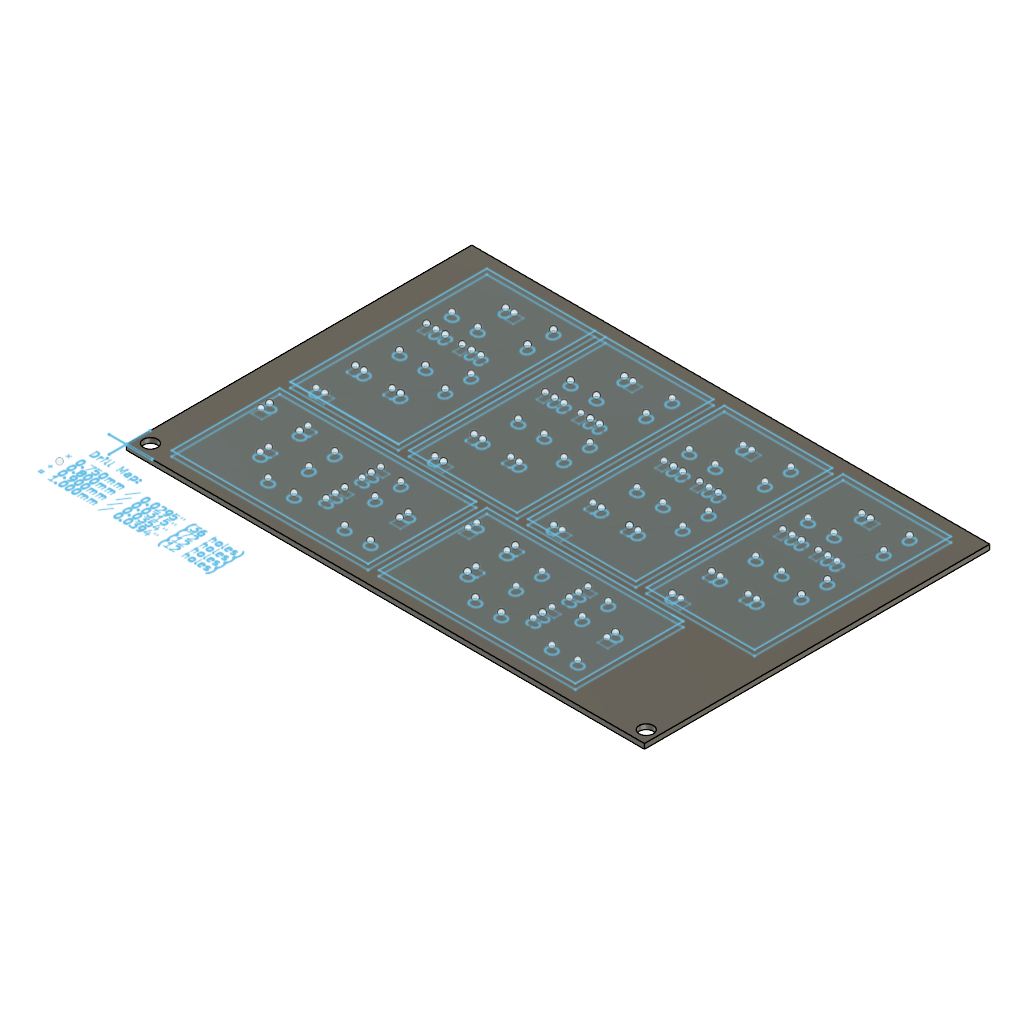
Pcb DXF's amd copper plate (Autodesk Fusion 360 archive; units mm, degrees)
design "Pcb DXF's amd copper plate"
part number: 2026-08-05-12-23-01-536
Autodesk Fusion 360 part; units mm, degrees
(part 1 of 28)
sketch "Sketch1" plane through (0, 0, 0) normal (0, 0, 1) x (1, 0, 0)
  line L0 (0, 0) -> (152.4, 0)
  line L1 (152.4, 0) -> (152.4, 101.6)
  line L2 (152.4, 101.6) -> (0, 101.6)
  line L3 (0, 101.6) -> (0, 0)
  dimension "d1" = 152.4
  dimension "d2" = 101.6
  constraint horizontal L0
  constraint vertical L1
  constraint horizontal L2
  constraint vertical L3
  constraint coincident L0.start L3.end
  measures "d1" distance of L0.start L0.end
  measures "d2" distance of L0.start L2.end
extrude "Extrude1" add sketch "Sketch1" along normal blind 1.4859
sketch "Sketch2" plane through (0, 0, 1.4859) normal (0, 0, 1) x (-1, 0, 0)
  line L0 (0, -101.6) -> (0, 0)
  line L1 (0, 0) -> (-152.4, 0)
  line L2 (-152.4, 0) -> (-152.4, -101.6)
  line L3 (-152.4, -101.6) -> (0, -101.6)
  circle A0 centre (-3.2766, -3.81) radius 2.0955
  line L4 (-3.2766, -3.81) -> (-149.1234, -3.81)
  circle A1 centre (-149.1234, -3.81) radius 2.0955
  line L5 (-76.2, -101.6) -> (-76.2, 0) construction
  line L6 (-76.2, -3.81) -> (-76.2, 5.8552) construction
  dimension "d5" = 4.191
  dimension "d8" = 145.8468
  dimension "d9" = 4.191
  constraint coincident A0.centre L4.start
  constraint perpendicular L0 L4
  constraint coincident L4.end A1.centre
  constraint midpoint L3 L5.start
  constraint midpoint L1 L5.end
  constraint midpoint L4 L6.start
  constraint perpendicular L4 L6
  measures "d5" diameter of A0
  measures "d8" distance of A0.centre L4.end
  measures "d9" diameter of A1
extrude "Extrude2" cut sketch "Sketch2" against normal blind 7.62 contours A0 | A1
sketch "Blinking Light House-Edge_Cuts" plane through (0, 0, 1.4859) normal (0, 0, 1) x (1, 0, 0)
  line L0 (0.0231, 6.9946) -> (0.025, 6.985)
  line L1 (0.025, 6.985) -> (0.025, 0.025)
  line L2 (0.025, 0.025) -> (7.62, 0.025)
  line L3 (7.62, 0.025) -> (7.6296, 0.0231)
  line L4 (7.6296, 0.0231) -> (7.6431, 0.0096)
  line L5 (7.6431, 0.0096) -> (7.6431, -0.0096)
  line L6 (7.6431, -0.0096) -> (7.6296, -0.0231)
  line L7 (7.6296, -0.0231) -> (7.62, -0.025)
  line L8 (7.62, -0.025) -> (0.025, -0.025)
  line L9 (0.025, -0.025) -> (0.025, -5.08)
  line L10 (0.025, -5.08) -> (0.0231, -5.0896)
  line L11 (0.0231, -5.0896) -> (0.0096, -5.1031)
  line L12 (0.0096, -5.1031) -> (-0.0096, -5.1031)
  line L13 (-0.0096, -5.1031) -> (-0.0231, -5.0896)
  line L14 (-0.0231, -5.0896) -> (-0.025, -5.08)
  line L15 (-0.025, -5.08) -> (-0.025, -0.025)
  line L16 (-0.025, -0.025) -> (-5.08, -0.025)
  line L17 (-5.08, -0.025) -> (-5.0896, -0.0231)
  line L18 (-5.0896, -0.0231) -> (-5.1031, -0.0096)
  line L19 (-5.1031, -0.0096) -> (-5.1031, 0.0096)
  line L20 (-5.1031, 0.0096) -> (-5.0896, 0.0231)
  line L21 (-5.0896, 0.0231) -> (-5.08, 0.025)
  line L22 (-5.08, 0.025) -> (-0.025, 0.025)
  line L23 (-0.025, 0.025) -> (-0.025, 6.985)
  line L24 (-0.025, 6.985) -> (-0.0231, 6.9946)
  line L25 (-0.0231, 6.9946) -> (-0.0096, 7.0081)
  line L26 (-0.0096, 7.0081) -> (0.0096, 7.0081)
  line L27 (0.0096, 7.0081) -> (0.0231, 6.9946)
  line L28 (66.04, 36.855) -> (66.0496, 36.8531)
  line L29 (66.0496, 36.8531) -> (66.0631, 36.8396)
  line L30 (66.0631, 36.8396) -> (66.065, 36.83)
  line L31 (66.065, 36.83) -> (66.065, 5.08)
  line L32 (66.065, 5.08) -> (66.0631, 5.0704)
  line L33 (66.0631, 5.0704) -> (66.0496, 5.0569)
  line L34 (66.0496, 5.0569) -> (66.04, 5.055)
  line L35 (66.04, 5.055) -> (8.255, 5.055)
  line L36 (8.255, 5.055) -> (8.2454, 5.0569)
  line L37 (8.2454, 5.0569) -> (8.2319, 5.0704)
  line L38 (8.2319, 5.0704) -> (8.23, 5.08)
  line L39 (8.23, 5.08) -> (8.23, 36.83)
  line L40 (8.23, 36.83) -> (8.2319, 36.8396)
  line L41 (8.2319, 36.8396) -> (8.2454, 36.8531)
  line L42 (8.2454, 36.8531) -> (8.255, 36.855)
  line L43 (8.255, 36.855) -> (66.04, 36.855)
  line L44 (8.28, 36.805) -> (8.28, 5.105)
  line L45 (8.28, 5.105) -> (66.015, 5.105)
  line L46 (66.015, 5.105) -> (66.015, 36.805)
  line L47 (66.015, 36.805) -> (62.865, 36.805)
  line L48 (62.865, 36.805) -> (8.28, 36.805)
  line L49 (127, 36.855) -> (127.0096, 36.8531)
  line L50 (127.0096, 36.8531) -> (127.0231, 36.8396)
  line L51 (127.0231, 36.8396) -> (127.025, 36.83)
  line L52 (127.025, 36.83) -> (127.025, 5.08)
  line L53 (127.025, 5.08) -> (127.0231, 5.0704)
  line L54 (127.0231, 5.0704) -> (127.0096, 5.0569)
  line L55 (127.0096, 5.0569) -> (127, 5.055)
  line L56 (127, 5.055) -> (69.215, 5.055)
  line L57 (69.215, 5.055) -> (69.2054, 5.0569)
  line L58 (69.2054, 5.0569) -> (69.1919, 5.0704)
  line L59 (69.1919, 5.0704) -> (69.19, 5.08)
  line L60 (69.19, 5.08) -> (69.19, 36.83)
  line L61 (69.19, 36.83) -> (69.1919, 36.8396)
  line L62 (69.1919, 36.8396) -> (69.2054, 36.8531)
  line L63 (69.2054, 36.8531) -> (69.215, 36.855)
  line L64 (69.215, 36.855) -> (127, 36.855)
  line L65 (69.24, 36.805) -> (69.24, 5.105)
  line L66 (69.24, 5.105) -> (126.975, 5.105)
  line L67 (126.975, 5.105) -> (126.975, 36.805)
  line L68 (126.975, 36.805) -> (123.825, 36.805)
  line L69 (123.825, 36.805) -> (69.24, 36.805)
  line L70 (43.18, 97.815) -> (74.93, 97.815)
  line L71 (74.93, 97.815) -> (74.9396, 97.8131)
  line L72 (74.9396, 97.8131) -> (74.9531, 97.7996)
  line L73 (74.9531, 97.7996) -> (74.955, 97.79)
  line L74 (74.955, 97.79) -> (74.955, 40.005)
  line L75 (74.955, 40.005) -> (74.9531, 39.9954)
  line L76 (74.9531, 39.9954) -> (74.9396, 39.9819)
  line L77 (74.9396, 39.9819) -> (74.93, 39.98)
  line L78 (74.93, 39.98) -> (43.18, 39.98)
  line L79 (43.18, 39.98) -> (43.1704, 39.9819)
  line L80 (43.1704, 39.9819) -> (43.1569, 39.9954)
  line L81 (43.1569, 39.9954) -> (43.155, 40.005)
  line L82 (43.155, 40.005) -> (43.155, 97.765)
  line L83 (40.03, 97.765) -> (40.03, 40.005)
  line L84 (40.03, 40.005) -> (40.0281, 39.9954)
  line L85 (40.0281, 39.9954) -> (40.0146, 39.9819)
  line L86 (40.0146, 39.9819) -> (40.005, 39.98)
  line L87 (40.005, 39.98) -> (8.255, 39.98)
  line L88 (8.255, 39.98) -> (8.2454, 39.9819)
  line L89 (8.2454, 39.9819) -> (8.2319, 39.9954)
  line L90 (8.2319, 39.9954) -> (8.23, 40.005)
  line L91 (8.23, 40.005) -> (8.23, 97.79)
  line L92 (8.23, 97.79) -> (8.2319, 97.7996)
  line L93 (8.2319, 97.7996) -> (8.2454, 97.8131)
  line L94 (8.2454, 97.8131) -> (8.255, 97.815)
  line L95 (8.255, 97.815) -> (40.005, 97.815)
  line L96 (43.205, 97.765) -> (43.205, 40.03)
  line L97 (43.205, 40.03) -> (74.905, 40.03)
  line L98 (74.905, 40.03) -> (74.905, 97.765)
  line L99 (74.905, 97.765) -> (43.205, 97.765)
  line L100 (8.28, 97.765) -> (8.28, 40.03)
  line L101 (8.28, 40.03) -> (39.98, 40.03)
  line L102 (39.98, 40.03) -> (39.98, 97.765)
  line L103 (39.98, 97.765) -> (8.28, 97.765)
  line L104 (109.8646, 97.8131) -> (109.8781, 97.7996)
  line L105 (109.8781, 97.7996) -> (109.88, 97.79)
  line L106 (109.88, 97.79) -> (109.88, 40.005)
  line L107 (109.88, 40.005) -> (109.8781, 39.9954)
  line L108 (109.8781, 39.9954) -> (109.8646, 39.9819)
  line L109 (109.8646, 39.9819) -> (109.855, 39.98)
  line L110 (109.855, 39.98) -> (78.105, 39.98)
  line L111 (78.105, 39.98) -> (78.0954, 39.9819)
  line L112 (78.0954, 39.9819) -> (78.0819, 39.9954)
  line L113 (78.0819, 39.9954) -> (78.08, 40.005)
  line L114 (78.08, 40.005) -> (78.08, 97.79)
  line L115 (78.08, 97.79) -> (78.0819, 97.7996)
  line L116 (78.0819, 97.7996) -> (78.0954, 97.8131)
  line L117 (78.0954, 97.8131) -> (78.105, 97.815)
  line L118 (78.105, 97.815) -> (109.855, 97.815)
  line L119 (109.855, 97.815) -> (109.8646, 97.8131)
  line L120 (78.13, 97.765) -> (78.13, 40.03)
  line L121 (78.13, 40.03) -> (109.83, 40.03)
  line L122 (109.83, 40.03) -> (109.83, 97.765)
  line L123 (109.83, 97.765) -> (78.13, 97.765)
  line L124 (144.7896, 97.8131) -> (144.8031, 97.7996)
  line L125 (144.8031, 97.7996) -> (144.805, 97.79)
  line L126 (144.805, 97.79) -> (144.805, 40.005)
  line L127 (144.805, 40.005) -> (144.8031, 39.9954)
  line L128 (144.8031, 39.9954) -> (144.7896, 39.9819)
  line L129 (144.7896, 39.9819) -> (144.78, 39.98)
  line L130 (144.78, 39.98) -> (113.03, 39.98)
  line L131 (113.03, 39.98) -> (113.0204, 39.9819)
  line L132 (113.0204, 39.9819) -> (113.0069, 39.9954)
  line L133 (113.0069, 39.9954) -> (113.005, 40.005)
  line L134 (113.005, 40.005) -> (113.005, 97.79)
  line L135 (113.005, 97.79) -> (113.0069, 97.7996)
  line L136 (113.0069, 97.7996) -> (113.0204, 97.8131)
  line L137 (113.0204, 97.8131) -> (113.03, 97.815)
  line L138 (113.03, 97.815) -> (144.78, 97.815)
  line L139 (144.78, 97.815) -> (144.7896, 97.8131)
  line L140 (113.055, 97.765) -> (113.055, 40.03)
  line L141 (113.055, 40.03) -> (144.755, 40.03)
  line L142 (144.755, 40.03) -> (144.755, 97.765)
  line L143 (144.755, 97.765) -> (113.055, 97.765)
sketch "Blinking Light House-B_Cu" plane through (0, 0, 1.4859) normal (0, 0, 1) x (1, 0, 0)
  line L0 (53.0106, 12.7385, -1.4859) -> (53.2043, 12.7078, -1.4859)
  line L1 (53.2043, 12.7078, -1.4859) -> (53.3909, 12.6472, -1.4859)
  line L2 (53.3909, 12.6472, -1.4859) -> (53.5657, 12.5581, -1.4859)
  line L3 (53.5657, 12.5581, -1.4859) -> (53.7243, 12.4428, -1.4859)
  line L4 (53.7243, 12.4428, -1.4859) -> (53.863, 12.3041, -1.4859)
  line L5 (53.863, 12.3041, -1.4859) -> (53.9783, 12.1454, -1.4859)
  line L6 (53.9783, 12.1454, -1.4859) -> (54.0674, 11.9707, -1.4859)
  line L7 (54.0674, 11.9707, -1.4859) -> (54.128, 11.7841, -1.4859)
  line L8 (54.128, 11.7841, -1.4859) -> (54.1587, 11.5904, -1.4859)
  line L9 (54.1587, 11.5904, -1.4859) -> (54.1587, 11.3942, -1.4859)
  line L10 (54.1587, 11.3942, -1.4859) -> (54.128, 11.2005, -1.4859)
  line L11 (54.128, 11.2005, -1.4859) -> (54.0674, 11.014, -1.4859)
  line L12 (54.0674, 11.014, -1.4859) -> (53.9783, 10.8392, -1.4859)
  line L13 (53.9783, 10.8392, -1.4859) -> (53.863, 10.6805, -1.4859)
  line L14 (53.863, 10.6805, -1.4859) -> (53.7243, 10.5418, -1.4859)
  line L15 (53.7243, 10.5418, -1.4859) -> (53.5657, 10.4265, -1.4859)
  line L16 (53.5657, 10.4265, -1.4859) -> (53.3909, 10.3375, -1.4859)
  line L17 (53.3909, 10.3375, -1.4859) -> (53.2043, 10.2768, -1.4859)
  line L18 (53.2043, 10.2768, -1.4859) -> (53.0106, 10.2462, -1.4859)
  line L19 (53.0106, 10.2462, -1.4859) -> (52.9125, 10.2423, -1.4859)
  line L20 (52.9125, 10.2423, -1.4859) -> (52.4125, 10.2423, -1.4859)
  line L21 (52.4125, 10.2423, -1.4859) -> (52.3145, 10.2462, -1.4859)
  line L22 (52.3145, 10.2462, -1.4859) -> (52.1207, 10.2768, -1.4859)
  line L23 (52.1207, 10.2768, -1.4859) -> (51.9342, 10.3375, -1.4859)
  line L24 (51.9342, 10.3375, -1.4859) -> (51.7594, 10.4265, -1.4859)
  line L25 (51.7594, 10.4265, -1.4859) -> (51.6007, 10.5418, -1.4859)
  line L26 (51.6007, 10.5418, -1.4859) -> (51.462, 10.6805, -1.4859)
  line L27 (51.462, 10.6805, -1.4859) -> (51.3467, 10.8392, -1.4859)
  line L28 (51.3467, 10.8392, -1.4859) -> (51.2577, 11.014, -1.4859)
  line L29 (51.2577, 11.014, -1.4859) -> (51.1971, 11.2005, -1.4859)
  line L30 (51.1971, 11.2005, -1.4859) -> (51.1664, 11.3942, -1.4859)
  line L31 (51.1664, 11.3942, -1.4859) -> (51.1664, 11.5904, -1.4859)
  line L32 (51.1664, 11.5904, -1.4859) -> (51.1971, 11.7841, -1.4859)
  line L33 (51.1971, 11.7841, -1.4859) -> (51.2577, 11.9707, -1.4859)
  line L34 (51.2577, 11.9707, -1.4859) -> (51.3467, 12.1454, -1.4859)
  line L35 (51.3467, 12.1454, -1.4859) -> (51.462, 12.3041, -1.4859)
  line L36 (51.462, 12.3041, -1.4859) -> (51.6007, 12.4428, -1.4859)
  line L37 (51.6007, 12.4428, -1.4859) -> (51.7594, 12.5581, -1.4859)
  line L38 (51.7594, 12.5581, -1.4859) -> (51.9342, 12.6472, -1.4859)
  line L39 (51.9342, 12.6472, -1.4859) -> (52.1207, 12.7078, -1.4859)
  line L40 (52.1207, 12.7078, -1.4859) -> (52.3145, 12.7385, -1.4859)
  line L41 (52.3145, 12.7385, -1.4859) -> (52.4125, 12.7423, -1.4859)
  line L42 (52.4125, 12.7423, -1.4859) -> (52.9125, 12.7423, -1.4859)
  line L43 (52.9125, 12.7423, -1.4859) -> (53.0106, 12.7385, -1.4859)
  line L44 (60.6306, 12.7385, -1.4859) -> (60.8243, 12.7078, -1.4859)
  line L45 (60.8243, 12.7078, -1.4859) -> (61.0109, 12.6472, -1.4859)
  line L46 (61.0109, 12.6472, -1.4859) -> (61.1857, 12.5581, -1.4859)
  line L47 (61.1857, 12.5581, -1.4859) -> (61.3443, 12.4428, -1.4859)
  line L48 (61.3443, 12.4428, -1.4859) -> (61.483, 12.3041, -1.4859)
  line L49 (61.483, 12.3041, -1.4859) -> (61.5983, 12.1454, -1.4859)
  line L50 (61.5983, 12.1454, -1.4859) -> (61.6874, 11.9707, -1.4859)
  line L51 (61.6874, 11.9707, -1.4859) -> (61.748, 11.7841, -1.4859)
  line L52 (61.748, 11.7841, -1.4859) -> (61.7787, 11.5904, -1.4859)
  line L53 (61.7787, 11.5904, -1.4859) -> (61.7787, 11.3942, -1.4859)
  line L54 (61.7787, 11.3942, -1.4859) -> (61.748, 11.2005, -1.4859)
  line L55 (61.748, 11.2005, -1.4859) -> (61.6874, 11.014, -1.4859)
  line L56 (61.6874, 11.014, -1.4859) -> (61.5983, 10.8392, -1.4859)
  line L57 (61.5983, 10.8392, -1.4859) -> (61.483, 10.6805, -1.4859)
  line L58 (61.483, 10.6805, -1.4859) -> (61.3443, 10.5418, -1.4859)
  line L59 (61.3443, 10.5418, -1.4859) -> (61.1857, 10.4265, -1.4859)
  line L60 (61.1857, 10.4265, -1.4859) -> (61.0109, 10.3375, -1.4859)
  line L61 (61.0109, 10.3375, -1.4859) -> (60.8243, 10.2768, -1.4859)
  line L62 (60.8243, 10.2768, -1.4859) -> (60.6306, 10.2462, -1.4859)
  line L63 (60.6306, 10.2462, -1.4859) -> (60.5325, 10.2423, -1.4859)
  line L64 (60.5325, 10.2423, -1.4859) -> (60.0325, 10.2423, -1.4859)
  line L65 (60.0325, 10.2423, -1.4859) -> (59.9345, 10.2462, -1.4859)
  line L66 (59.9345, 10.2462, -1.4859) -> (59.7407, 10.2768, -1.4859)
  line L67 (59.7407, 10.2768, -1.4859) -> (59.5542, 10.3375, -1.4859)
  line L68 (59.5542, 10.3375, -1.4859) -> (59.3794, 10.4265, -1.4859)
  line L69 (59.3794, 10.4265, -1.4859) -> (59.2207, 10.5418, -1.4859)
  line L70 (59.2207, 10.5418, -1.4859) -> (59.082, 10.6805, -1.4859)
  line L71 (59.082, 10.6805, -1.4859) -> (58.9667, 10.8392, -1.4859)
  line L72 (58.9667, 10.8392, -1.4859) -> (58.8777, 11.014, -1.4859)
  line L73 (58.8777, 11.014, -1.4859) -> (58.8171, 11.2005, -1.4859)
  line L74 (58.8171, 11.2005, -1.4859) -> (58.7864, 11.3942, -1.4859)
  line L75 (58.7864, 11.3942, -1.4859) -> (58.7864, 11.5904, -1.4859)
  line L76 (58.7864, 11.5904, -1.4859) -> (58.8171, 11.7841, -1.4859)
  line L77 (58.8171, 11.7841, -1.4859) -> (58.8777, 11.9707, -1.4859)
  line L78 (58.8777, 11.9707, -1.4859) -> (58.9667, 12.1454, -1.4859)
  line L79 (58.9667, 12.1454, -1.4859) -> (59.082, 12.3041, -1.4859)
  line L80 (59.082, 12.3041, -1.4859) -> (59.2207, 12.4428, -1.4859)
  line L81 (59.2207, 12.4428, -1.4859) -> (59.3794, 12.5581, -1.4859)
  line L82 (59.3794, 12.5581, -1.4859) -> (59.5542, 12.6472, -1.4859)
  line L83 (59.5542, 12.6472, -1.4859) -> (59.7407, 12.7078, -1.4859)
  line L84 (59.7407, 12.7078, -1.4859) -> (59.9345, 12.7385, -1.4859)
  line L85 (59.9345, 12.7385, -1.4859) -> (60.0325, 12.7423, -1.4859)
  line L86 (60.0325, 12.7423, -1.4859) -> (60.5325, 12.7423, -1.4859)
  line L87 (60.5325, 12.7423, -1.4859) -> (60.6306, 12.7385, -1.4859)
  line L88 (113.9706, 12.7385, -1.4859) -> (114.1643, 12.7078, -1.4859)
  line L89 (114.1643, 12.7078, -1.4859) -> (114.3509, 12.6472, -1.4859)
  line L90 (114.3509, 12.6472, -1.4859) -> (114.5257, 12.5581, -1.4859)
  line L91 (114.5257, 12.5581, -1.4859) -> (114.6843, 12.4428, -1.4859)
  line L92 (114.6843, 12.4428, -1.4859) -> (114.823, 12.3041, -1.4859)
  line L93 (114.823, 12.3041, -1.4859) -> (114.9383, 12.1454, -1.4859)
  line L94 (114.9383, 12.1454, -1.4859) -> (115.0274, 11.9707, -1.4859)
  line L95 (115.0274, 11.9707, -1.4859) -> (115.088, 11.7841, -1.4859)
  line L96 (115.088, 11.7841, -1.4859) -> (115.1187, 11.5904, -1.4859)
  line L97 (115.1187, 11.5904, -1.4859) -> (115.1187, 11.3942, -1.4859)
  line L98 (115.1187, 11.3942, -1.4859) -> (115.088, 11.2005, -1.4859)
  line L99 (115.088, 11.2005, -1.4859) -> (115.0274, 11.014, -1.4859)
  line L100 (115.0274, 11.014, -1.4859) -> (114.9383, 10.8392, -1.4859)
  line L101 (114.9383, 10.8392, -1.4859) -> (114.823, 10.6805, -1.4859)
  line L102 (114.823, 10.6805, -1.4859) -> (114.6843, 10.5418, -1.4859)
  line L103 (114.6843, 10.5418, -1.4859) -> (114.5257, 10.4265, -1.4859)
  line L104 (114.5257, 10.4265, -1.4859) -> (114.3509, 10.3375, -1.4859)
  line L105 (114.3509, 10.3375, -1.4859) -> (114.1643, 10.2768, -1.4859)
  line L106 (114.1643, 10.2768, -1.4859) -> (113.9706, 10.2462, -1.4859)
  line L107 (113.9706, 10.2462, -1.4859) -> (113.8725, 10.2423, -1.4859)
  line L108 (113.8725, 10.2423, -1.4859) -> (113.3725, 10.2423, -1.4859)
  line L109 (113.3725, 10.2423, -1.4859) -> (113.2745, 10.2462, -1.4859)
  line L110 (113.2745, 10.2462, -1.4859) -> (113.0807, 10.2768, -1.4859)
  line L111 (113.0807, 10.2768, -1.4859) -> (112.8942, 10.3375, -1.4859)
  line L112 (112.8942, 10.3375, -1.4859) -> (112.7194, 10.4265, -1.4859)
  line L113 (112.7194, 10.4265, -1.4859) -> (112.5607, 10.5418, -1.4859)
  line L114 (112.5607, 10.5418, -1.4859) -> (112.422, 10.6805, -1.4859)
  line L115 (112.422, 10.6805, -1.4859) -> (112.3067, 10.8392, -1.4859)
  line L116 (112.3067, 10.8392, -1.4859) -> (112.2177, 11.014, -1.4859)
  line L117 (112.2177, 11.014, -1.4859) -> (112.1571, 11.2005, -1.4859)
  line L118 (112.1571, 11.2005, -1.4859) -> (112.1264, 11.3942, -1.4859)
  line L119 (112.1264, 11.3942, -1.4859) -> (112.1264, 11.5904, -1.4859)
  line L120 (112.1264, 11.5904, -1.4859) -> (112.1571, 11.7841, -1.4859)
  line L121 (112.1571, 11.7841, -1.4859) -> (112.2177, 11.9707, -1.4859)
  line L122 (112.2177, 11.9707, -1.4859) -> (112.3067, 12.1454, -1.4859)
  line L123 (112.3067, 12.1454, -1.4859) -> (112.422, 12.3041, -1.4859)
  line L124 (112.422, 12.3041, -1.4859) -> (112.5607, 12.4428, -1.4859)
  line L125 (112.5607, 12.4428, -1.4859) -> (112.7194, 12.5581, -1.4859)
  line L126 (112.7194, 12.5581, -1.4859) -> (112.8942, 12.6472, -1.4859)
  line L127 (112.8942, 12.6472, -1.4859) -> (113.0807, 12.7078, -1.4859)
  line L128 (113.0807, 12.7078, -1.4859) -> (113.2745, 12.7385, -1.4859)
  line L129 (113.2745, 12.7385, -1.4859) -> (113.3725, 12.7423, -1.4859)
  line L130 (113.3725, 12.7423, -1.4859) -> (113.8725, 12.7423, -1.4859)
  line L131 (113.8725, 12.7423, -1.4859) -> (113.9706, 12.7385, -1.4859)
  line L132 (121.5906, 12.7385, -1.4859) -> (121.7843, 12.7078, -1.4859)
  line L133 (121.7843, 12.7078, -1.4859) -> (121.9709, 12.6472, -1.4859)
  line L134 (121.9709, 12.6472, -1.4859) -> (122.1457, 12.5581, -1.4859)
  line L135 (122.1457, 12.5581, -1.4859) -> (122.3043, 12.4428, -1.4859)
  line L136 (122.3043, 12.4428, -1.4859) -> (122.443, 12.3041, -1.4859)
  line L137 (122.443, 12.3041, -1.4859) -> (122.5583, 12.1454, -1.4859)
  line L138 (122.5583, 12.1454, -1.4859) -> (122.6474, 11.9707, -1.4859)
  line L139 (122.6474, 11.9707, -1.4859) -> (122.708, 11.7841, -1.4859)
  line L140 (122.708, 11.7841, -1.4859) -> (122.7387, 11.5904, -1.4859)
  line L141 (122.7387, 11.5904, -1.4859) -> (122.7387, 11.3942, -1.4859)
  line L142 (122.7387, 11.3942, -1.4859) -> (122.708, 11.2005, -1.4859)
  line L143 (122.708, 11.2005, -1.4859) -> (122.6474, 11.014, -1.4859)
  line L144 (122.6474, 11.014, -1.4859) -> (122.5583, 10.8392, -1.4859)
  line L145 (122.5583, 10.8392, -1.4859) -> (122.443, 10.6805, -1.4859)
  line L146 (122.443, 10.6805, -1.4859) -> (122.3043, 10.5418, -1.4859)
  line L147 (122.3043, 10.5418, -1.4859) -> (122.1457, 10.4265, -1.4859)
  line L148 (122.1457, 10.4265, -1.4859) -> (121.9709, 10.3375, -1.4859)
  line L149 (121.9709, 10.3375, -1.4859) -> (121.7843, 10.2768, -1.4859)
  line L150 (121.7843, 10.2768, -1.4859) -> (121.5906, 10.2462, -1.4859)
  line L151 (121.5906, 10.2462, -1.4859) -> (121.4925, 10.2423, -1.4859)
  line L152 (121.4925, 10.2423, -1.4859) -> (120.9925, 10.2423, -1.4859)
  line L153 (120.9925, 10.2423, -1.4859) -> (120.8945, 10.2462, -1.4859)
  line L154 (120.8945, 10.2462, -1.4859) -> (120.7007, 10.2768, -1.4859)
  line L155 (120.7007, 10.2768, -1.4859) -> (120.5142, 10.3375, -1.4859)
  line L156 (120.5142, 10.3375, -1.4859) -> (120.3394, 10.4265, -1.4859)
  line L157 (120.3394, 10.4265, -1.4859) -> (120.1807, 10.5418, -1.4859)
  line L158 (120.1807, 10.5418, -1.4859) -> (120.042, 10.6805, -1.4859)
  line L159 (120.042, 10.6805, -1.4859) -> (119.9267, 10.8392, -1.4859)
  line L160 (119.9267, 10.8392, -1.4859) -> (119.8377, 11.014, -1.4859)
  line L161 (119.8377, 11.014, -1.4859) -> (119.7771, 11.2005, -1.4859)
  line L162 (119.7771, 11.2005, -1.4859) -> (119.7464, 11.3942, -1.4859)
  line L163 (119.7464, 11.3942, -1.4859) -> (119.7464, 11.5904, -1.4859)
  line L164 (119.7464, 11.5904, -1.4859) -> (119.7771, 11.7841, -1.4859)
  line L165 (119.7771, 11.7841, -1.4859) -> (119.8377, 11.9707, -1.4859)
  line L166 (119.8377, 11.9707, -1.4859) -> (119.9267, 12.1454, -1.4859)
  line L167 (119.9267, 12.1454, -1.4859) -> (120.042, 12.3041, -1.4859)
  line L168 (120.042, 12.3041, -1.4859) -> (120.1807, 12.4428, -1.4859)
  line L169 (120.1807, 12.4428, -1.4859) -> (120.3394, 12.5581, -1.4859)
  line L170 (120.3394, 12.5581, -1.4859) -> (120.5142, 12.6472, -1.4859)
  line L171 (120.5142, 12.6472, -1.4859) -> (120.7007, 12.7078, -1.4859)
  line L172 (120.7007, 12.7078, -1.4859) -> (120.8945, 12.7385, -1.4859)
  line L173 (120.8945, 12.7385, -1.4859) -> (120.9925, 12.7423, -1.4859)
  line L174 (120.9925, 12.7423, -1.4859) -> (121.4925, 12.7423, -1.4859)
  line L175 (121.4925, 12.7423, -1.4859) -> (121.5906, 12.7385, -1.4859)
  line L176 (29.6648, 13.5881, -1.4859) -> (29.8585, 13.5574, -1.4859)
  line L177 (29.8585, 13.5574, -1.4859) -> (30.0451, 13.4968, -1.4859)
  line L178 (30.0451, 13.4968, -1.4859) -> (30.2199, 13.4078, -1.4859)
  line L179 (30.2199, 13.4078, -1.4859) -> (30.3786, 13.2925, -1.4859)
  line L180 (30.3786, 13.2925, -1.4859) -> (30.5172, 13.1538, -1.4859)
  line L181 (30.5172, 13.1538, -1.4859) -> (30.6325, 12.9951, -1.4859)
  line L182 (30.6325, 12.9951, -1.4859) -> (30.7216, 12.8203, -1.4859)
  line L183 (30.7216, 12.8203, -1.4859) -> (30.7822, 12.6338, -1.4859)
  line L184 (30.7822, 12.6338, -1.4859) -> (30.8129, 12.44, -1.4859)
  line L185 (30.8129, 12.44, -1.4859) -> (30.8129, 12.2439, -1.4859)
  line L186 (30.8129, 12.2439, -1.4859) -> (30.7822, 12.0501, -1.4859)
  line L187 (30.7822, 12.0501, -1.4859) -> (30.7216, 11.8636, -1.4859)
  line L188 (30.7216, 11.8636, -1.4859) -> (30.6325, 11.6888, -1.4859)
  line L189 (30.6325, 11.6888, -1.4859) -> (30.5172, 11.5301, -1.4859)
  line L190 (30.5172, 11.5301, -1.4859) -> (30.3786, 11.3914, -1.4859)
  line L191 (30.3786, 11.3914, -1.4859) -> (30.2199, 11.2762, -1.4859)
  line L192 (30.2199, 11.2762, -1.4859) -> (30.0451, 11.1871, -1.4859)
  line L193 (30.0451, 11.1871, -1.4859) -> (29.8585, 11.1265, -1.4859)
  line L194 (29.8585, 11.1265, -1.4859) -> (29.6648, 11.0958, -1.4859)
  line L195 (29.6648, 11.0958, -1.4859) -> (29.5667, 11.092, -1.4859)
  line L196 (29.5667, 11.092, -1.4859) -> (29.0667, 11.092, -1.4859)
  line L197 (29.0667, 11.092, -1.4859) -> (28.9687, 11.0958, -1.4859)
  line L198 (28.9687, 11.0958, -1.4859) -> (28.7749, 11.1265, -1.4859)
  line L199 (28.7749, 11.1265, -1.4859) -> (28.5884, 11.1871, -1.4859)
  line L200 (28.5884, 11.1871, -1.4859) -> (28.4136, 11.2762, -1.4859)
  line L201 (28.4136, 11.2762, -1.4859) -> (28.2549, 11.3915, -1.4859)
  line L202 (28.2549, 11.3915, -1.4859) -> (28.1162, 11.5301, -1.4859)
  line L203 (28.1162, 11.5301, -1.4859) -> (28.0009, 11.6888, -1.4859)
  line L204 (28.0009, 11.6888, -1.4859) -> (27.9119, 11.8636, -1.4859)
  line L205 (27.9119, 11.8636, -1.4859) -> (27.8513, 12.0501, -1.4859)
  line L206 (27.8513, 12.0501, -1.4859) -> (27.8206, 12.2439, -1.4859)
  line L207 (27.8206, 12.2439, -1.4859) -> (27.8206, 12.44, -1.4859)
  line L208 (27.8206, 12.44, -1.4859) -> (27.8513, 12.6338, -1.4859)
  line L209 (27.8513, 12.6338, -1.4859) -> (27.9119, 12.8203, -1.4859)
  line L210 (27.9119, 12.8203, -1.4859) -> (28.0009, 12.9951, -1.4859)
  line L211 (28.0009, 12.9951, -1.4859) -> (28.1162, 13.1538, -1.4859)
  line L212 (28.1162, 13.1538, -1.4859) -> (28.2549, 13.2925, -1.4859)
  line L213 (28.2549, 13.2925, -1.4859) -> (28.4136, 13.4078, -1.4859)
  line L214 (28.4136, 13.4078, -1.4859) -> (28.5884, 13.4968, -1.4859)
  line L215 (28.5884, 13.4968, -1.4859) -> (28.7749, 13.5574, -1.4859)
  line L216 (28.7749, 13.5574, -1.4859) -> (28.9687, 13.5881, -1.4859)
  line L217 (28.9687, 13.5881, -1.4859) -> (29.0667, 13.592, -1.4859)
  line L218 (29.0667, 13.592, -1.4859) -> (29.5667, 13.592, -1.4859)
  line L219 (29.5667, 13.592, -1.4859) -> (29.6648, 13.5881, -1.4859)
  line L220 (12.0238, 28.3427, -1.4859) -> (14.7885, 25.5781, -1.4859)
  line L221 (14.7885, 25.5781, -1.4859) -> (24.1374, 25.5781, -1.4859)
  line L222 (24.1374, 25.5781, -1.4859) -> (24.2157, 25.5729, -1.4859)
  line L223 (24.2157, 25.5729, -1.4859) -> (24.367, 25.5324, -1.4859)
  line L224 (24.367, 25.5324, -1.4859) -> (24.5026, 25.4541, -1.4859)
  line L225 (24.5026, 25.4541, -1.4859) -> (24.5616, 25.4023, -1.4859)
  line L226 (24.5616, 25.4023, -1.4859) -> (28.1119, 21.8521, -1.4859)
  line L227 (28.1119, 21.8521, -1.4859) -> (31.2002, 21.8521, -1.4859)
  line L228 (31.2002, 21.8521, -1.4859) -> (31.2419, 21.9805, -1.4859)
  line L229 (31.2419, 21.9805, -1.4859) -> (31.331, 22.1552, -1.4859)
  line L230 (31.331, 22.1552, -1.4859) -> (31.4463, 22.3139, -1.4859)
  line L231 (31.4463, 22.3139, -1.4859) -> (31.585, 22.4526, -1.4859)
  line L232 (31.585, 22.4526, -1.4859) -> (31.7436, 22.5679, -1.4859)
  line L233 (31.7436, 22.5679, -1.4859) -> (31.9184, 22.657, -1.4859)
  line L234 (31.9184, 22.657, -1.4859) -> (32.105, 22.7176, -1.4859)
  line L235 (32.105, 22.7176, -1.4859) -> (32.2987, 22.7483, -1.4859)
  line L236 (32.2987, 22.7483, -1.4859) -> (32.4948, 22.7483, -1.4859)
  line L237 (32.4948, 22.7483, -1.4859) -> (32.6886, 22.7176, -1.4859)
  line L238 (32.6886, 22.7176, -1.4859) -> (32.8751, 22.657, -1.4859)
  line L239 (32.8751, 22.657, -1.4859) -> (33.0499, 22.5679, -1.4859)
  line L240 (33.0499, 22.5679, -1.4859) -> (33.2086, 22.4526, -1.4859)
  line L241 (33.2086, 22.4526, -1.4859) -> (33.3473, 22.3139, -1.4859)
  line L242 (33.3473, 22.3139, -1.4859) -> (33.4626, 22.1552, -1.4859)
  line L243 (33.4626, 22.1552, -1.4859) -> (33.5516, 21.9805, -1.4859)
  line L244 (33.5516, 21.9805, -1.4859) -> (33.6122, 21.7939, -1.4859)
  line L245 (33.6122, 21.7939, -1.4859) -> (33.6429, 21.6002, -1.4859)
  line L246 (33.6429, 21.6002, -1.4859) -> (33.6468, 21.5021, -1.4859)
  line L247 (33.6468, 21.5021, -1.4859) -> (33.6468, 21.0021, -1.4859)
  line L248 (33.6468, 21.0021, -1.4859) -> (33.6429, 20.904, -1.4859)
  line L249 (33.6429, 20.904, -1.4859) -> (33.6122, 20.7103, -1.4859)
  line L250 (33.6122, 20.7103, -1.4859) -> (33.5516, 20.5238, -1.4859)
  line L251 (33.5516, 20.5238, -1.4859) -> (33.4626, 20.349, -1.4859)
  line L252 (33.4626, 20.349, -1.4859) -> (33.3473, 20.1903, -1.4859)
  line L253 (33.3473, 20.1903, -1.4859) -> (33.2086, 20.0516, -1.4859)
  line L254 (33.2086, 20.0516, -1.4859) -> (33.0499, 19.9363, -1.4859)
  line L255 (33.0499, 19.9363, -1.4859) -> (32.9968, 19.9092, -1.4859)
  line L256 (32.9968, 19.9092, -1.4859) -> (32.9968, 17.1305, -1.4859)
  line L257 (32.9968, 17.1305, -1.4859) -> (36.5459, 13.5813, -1.4859)
  line L258 (36.5459, 13.5813, -1.4859) -> (36.5887, 13.5881, -1.4859)
  line L259 (36.5887, 13.5881, -1.4859) -> (36.6867, 13.592, -1.4859)
  line L260 (36.6867, 13.592, -1.4859) -> (37.1867, 13.592, -1.4859)
  line L261 (37.1867, 13.592, -1.4859) -> (37.2848, 13.5881, -1.4859)
  line L262 (37.2848, 13.5881, -1.4859) -> (37.4785, 13.5574, -1.4859)
  line L263 (37.4785, 13.5574, -1.4859) -> (37.6651, 13.4968, -1.4859)
  line L264 (37.6651, 13.4968, -1.4859) -> (37.8399, 13.4078, -1.4859)
  line L265 (37.8399, 13.4078, -1.4859) -> (37.9986, 13.2925, -1.4859)
  line L266 (37.9986, 13.2925, -1.4859) -> (38.1372, 13.1538, -1.4859)
  line L267 (38.1372, 13.1538, -1.4859) -> (38.2525, 12.9951, -1.4859)
  line L268 (38.2525, 12.9951, -1.4859) -> (38.3416, 12.8203, -1.4859)
  line L269 (38.3416, 12.8203, -1.4859) -> (38.4022, 12.6338, -1.4859)
  line L270 (38.4022, 12.6338, -1.4859) -> (38.4329, 12.44, -1.4859)
  line L271 (38.4329, 12.44, -1.4859) -> (38.4329, 12.2439, -1.4859)
  line L272 (38.4329, 12.2439, -1.4859) -> (38.4022, 12.0501, -1.4859)
  line L273 (38.4022, 12.0501, -1.4859) -> (38.3416, 11.8636, -1.4859)
  line L274 (38.3416, 11.8636, -1.4859) -> (38.2525, 11.6888, -1.4859)
  line L275 (38.2525, 11.6888, -1.4859) -> (38.1372, 11.5301, -1.4859)
  line L276 (38.1372, 11.5301, -1.4859) -> (37.9986, 11.3914, -1.4859)
  line L277 (37.9986, 11.3914, -1.4859) -> (37.8399, 11.2762, -1.4859)
  line L278 (37.8399, 11.2762, -1.4859) -> (37.6651, 11.1871, -1.4859)
  line L279 (37.6651, 11.1871, -1.4859) -> (37.4785, 11.1265, -1.4859)
  line L280 (37.4785, 11.1265, -1.4859) -> (37.2848, 11.0958, -1.4859)
  line L281 (37.2848, 11.0958, -1.4859) -> (37.1867, 11.092, -1.4859)
  line L282 (37.1867, 11.092, -1.4859) -> (36.6867, 11.092, -1.4859)
  line L283 (36.6867, 11.092, -1.4859) -> (36.5887, 11.0958, -1.4859)
  line L284 (36.5887, 11.0958, -1.4859) -> (36.3949, 11.1265, -1.4859)
  line L285 (36.3949, 11.1265, -1.4859) -> (36.2084, 11.1871, -1.4859)
  line L286 (36.2084, 11.1871, -1.4859) -> (36.0336, 11.2762, -1.4859)
  line L287 (36.0336, 11.2762, -1.4859) -> (35.8749, 11.3915, -1.4859)
  line L288 (35.8749, 11.3915, -1.4859) -> (35.7362, 11.5301, -1.4859)
  line L289 (35.7362, 11.5301, -1.4859) -> (35.6209, 11.6888, -1.4859)
  line L290 (35.6209, 11.6888, -1.4859) -> (35.5319, 11.8636, -1.4859)
  line L291 (35.5319, 11.8636, -1.4859) -> (35.4713, 12.0501, -1.4859)
  line L292 (35.4713, 12.0501, -1.4859) -> (35.4406, 12.2439, -1.4859)
  line L293 (35.4406, 12.2439, -1.4859) -> (35.4406, 12.44, -1.4859)
  line L294 (35.4406, 12.44, -1.4859) -> (35.4713, 12.6338, -1.4859)
  line L295 (35.4713, 12.6338, -1.4859) -> (35.5319, 12.8203, -1.4859)
  line L296 (35.5319, 12.8203, -1.4859) -> (35.5582, 12.872, -1.4859)
  line L297 (35.5582, 12.872, -1.4859) -> (31.9725, 16.4577, -1.4859)
  line L298 (31.9725, 16.4577, -1.4859) -> (31.9208, 16.5167, -1.4859)
  line L299 (31.9208, 16.5167, -1.4859) -> (31.8424, 16.6523, -1.4859)
  line L300 (31.8424, 16.6523, -1.4859) -> (31.8019, 16.8036, -1.4859)
  line L301 (31.8019, 16.8036, -1.4859) -> (31.7968, 16.8819, -1.4859)
  line L302 (31.7968, 16.8819, -1.4859) -> (31.7968, 19.9092, -1.4859)
  line L303 (31.7968, 19.9092, -1.4859) -> (31.7436, 19.9363, -1.4859)
  line L304 (31.7436, 19.9363, -1.4859) -> (31.585, 20.0516, -1.4859)
  line L305 (31.585, 20.0516, -1.4859) -> (31.4463, 20.1903, -1.4859)
  line L306 (31.4463, 20.1903, -1.4859) -> (31.331, 20.349, -1.4859)
  line L307 (31.331, 20.349, -1.4859) -> (31.2419, 20.5238, -1.4859)
  line L308 (31.2419, 20.5238, -1.4859) -> (31.2002, 20.6521, -1.4859)
  line L309 (31.2002, 20.6521, -1.4859) -> (27.8633, 20.6521, -1.4859)
  line L310 (27.8633, 20.6521, -1.4859) -> (27.785, 20.6572, -1.4859)
  line L311 (27.785, 20.6572, -1.4859) -> (27.6337, 20.6978, -1.4859)
  line L312 (27.6337, 20.6978, -1.4859) -> (27.4981, 20.7761, -1.4859)
  line L313 (27.4981, 20.7761, -1.4859) -> (27.4391, 20.8278, -1.4859)
  line L314 (27.4391, 20.8278, -1.4859) -> (23.8888, 24.3781, -1.4859)
  line L315 (23.8888, 24.3781, -1.4859) -> (14.54, 24.3781, -1.4859)
  line L316 (14.54, 24.3781, -1.4859) -> (14.4616, 24.3832, -1.4859)
  line L317 (14.4616, 24.3832, -1.4859) -> (14.3104, 24.4237, -1.4859)
  line L318 (14.3104, 24.4237, -1.4859) -> (14.1747, 24.5021, -1.4859)
  line L319 (14.1747, 24.5021, -1.4859) -> (14.1157, 24.5538, -1.4859)
  line L320 (14.1157, 24.5538, -1.4859) -> (10.9003, 27.7692, -1.4859)
  line L321 (10.9003, 27.7692, -1.4859) -> (9.0238, 27.7692, -1.4859)
  line L322 (9.0238, 27.7692, -1.4859) -> (9.0238, 30.2192, -1.4859)
  line L323 (9.0238, 30.2192, -1.4859) -> (12.0238, 30.2192, -1.4859)
  line L324 (12.0238, 30.2192, -1.4859) -> (12.0238, 28.3427, -1.4859)
  line L325 (90.6248, 13.5881, -1.4859) -> (90.8185, 13.5574, -1.4859)
  line L326 (90.8185, 13.5574, -1.4859) -> (91.0051, 13.4968, -1.4859)
  line L327 (91.0051, 13.4968, -1.4859) -> (91.1799, 13.4078, -1.4859)
  line L328 (91.1799, 13.4078, -1.4859) -> (91.3385, 13.2925, -1.4859)
  line L329 (91.3385, 13.2925, -1.4859) -> (91.4772, 13.1538, -1.4859)
  line L330 (91.4772, 13.1538, -1.4859) -> (91.5925, 12.9951, -1.4859)
  line L331 (91.5925, 12.9951, -1.4859) -> (91.6816, 12.8203, -1.4859)
  line L332 (91.6816, 12.8203, -1.4859) -> (91.7422, 12.6338, -1.4859)
  line L333 (91.7422, 12.6338, -1.4859) -> (91.7729, 12.44, -1.4859)
  line L334 (91.7729, 12.44, -1.4859) -> (91.7729, 12.2439, -1.4859)
  line L335 (91.7729, 12.2439, -1.4859) -> (91.7422, 12.0501, -1.4859)
  line L336 (91.7422, 12.0501, -1.4859) -> (91.6816, 11.8636, -1.4859)
  line L337 (91.6816, 11.8636, -1.4859) -> (91.5925, 11.6888, -1.4859)
  line L338 (91.5925, 11.6888, -1.4859) -> (91.4772, 11.5301, -1.4859)
  line L339 (91.4772, 11.5301, -1.4859) -> (91.3385, 11.3914, -1.4859)
  line L340 (91.3385, 11.3914, -1.4859) -> (91.1799, 11.2762, -1.4859)
  line L341 (91.1799, 11.2762, -1.4859) -> (91.0051, 11.1871, -1.4859)
  line L342 (91.0051, 11.1871, -1.4859) -> (90.8185, 11.1265, -1.4859)
  line L343 (90.8185, 11.1265, -1.4859) -> (90.6248, 11.0958, -1.4859)
  line L344 (90.6248, 11.0958, -1.4859) -> (90.5267, 11.092, -1.4859)
  line L345 (90.5267, 11.092, -1.4859) -> (90.0267, 11.092, -1.4859)
  line L346 (90.0267, 11.092, -1.4859) -> (89.9287, 11.0958, -1.4859)
  line L347 (89.9287, 11.0958, -1.4859) -> (89.7349, 11.1265, -1.4859)
  line L348 (89.7349, 11.1265, -1.4859) -> (89.5484, 11.1871, -1.4859)
  line L349 (89.5484, 11.1871, -1.4859) -> (89.3736, 11.2762, -1.4859)
  line L350 (89.3736, 11.2762, -1.4859) -> (89.2149, 11.3915, -1.4859)
  line L351 (89.2149, 11.3915, -1.4859) -> (89.0762, 11.5301, -1.4859)
  line L352 (89.0762, 11.5301, -1.4859) -> (88.9609, 11.6888, -1.4859)
  line L353 (88.9609, 11.6888, -1.4859) -> (88.8719, 11.8636, -1.4859)
  line L354 (88.8719, 11.8636, -1.4859) -> (88.8113, 12.0501, -1.4859)
  line L355 (88.8113, 12.0501, -1.4859) -> (88.7806, 12.2439, -1.4859)
  line L356 (88.7806, 12.2439, -1.4859) -> (88.7806, 12.44, -1.4859)
  line L357 (88.7806, 12.44, -1.4859) -> (88.8113, 12.6338, -1.4859)
  line L358 (88.8113, 12.6338, -1.4859) -> (88.8719, 12.8203, -1.4859)
  line L359 (88.8719, 12.8203, -1.4859) -> (88.9609, 12.9951, -1.4859)
  line L360 (88.9609, 12.9951, -1.4859) -> (89.0762, 13.1538, -1.4859)
  line L361 (89.0762, 13.1538, -1.4859) -> (89.2149, 13.2925, -1.4859)
  line L362 (89.2149, 13.2925, -1.4859) -> (89.3736, 13.4078, -1.4859)
  line L363 (89.3736, 13.4078, -1.4859) -> (89.5484, 13.4968, -1.4859)
  line L364 (89.5484, 13.4968, -1.4859) -> (89.7349, 13.5574, -1.4859)
  line L365 (89.7349, 13.5574, -1.4859) -> (89.9287, 13.5881, -1.4859)
  line L366 (89.9287, 13.5881, -1.4859) -> (90.0267, 13.592, -1.4859)
  line L367 (90.0267, 13.592, -1.4859) -> (90.5267, 13.592, -1.4859)
  line L368 (90.5267, 13.592, -1.4859) -> (90.6248, 13.5881, -1.4859)
  line L369 (72.9838, 28.3427, -1.4859) -> (75.7485, 25.5781, -1.4859)
  line L370 (75.7485, 25.5781, -1.4859) -> (85.0974, 25.5781, -1.4859)
  line L371 (85.0974, 25.5781, -1.4859) -> (85.1757, 25.5729, -1.4859)
  line L372 (85.1757, 25.5729, -1.4859) -> (85.327, 25.5324, -1.4859)
  line L373 (85.327, 25.5324, -1.4859) -> (85.4626, 25.4541, -1.4859)
  line L374 (85.4626, 25.4541, -1.4859) -> (85.5216, 25.4023, -1.4859)
  line L375 (85.5216, 25.4023, -1.4859) -> (89.0719, 21.8521, -1.4859)
  line L376 (89.0719, 21.8521, -1.4859) -> (92.1602, 21.8521, -1.4859)
  line L377 (92.1602, 21.8521, -1.4859) -> (92.2019, 21.9805, -1.4859)
  line L378 (92.2019, 21.9805, -1.4859) -> (92.291, 22.1552, -1.4859)
  line L379 (92.291, 22.1552, -1.4859) -> (92.4063, 22.3139, -1.4859)
  line L380 (92.4063, 22.3139, -1.4859) -> (92.545, 22.4526, -1.4859)
  line L381 (92.545, 22.4526, -1.4859) -> (92.7036, 22.5679, -1.4859)
  line L382 (92.7036, 22.5679, -1.4859) -> (92.8784, 22.657, -1.4859)
  line L383 (92.8784, 22.657, -1.4859) -> (93.065, 22.7176, -1.4859)
  line L384 (93.065, 22.7176, -1.4859) -> (93.2587, 22.7483, -1.4859)
  line L385 (93.2587, 22.7483, -1.4859) -> (93.4548, 22.7483, -1.4859)
  line L386 (93.4548, 22.7483, -1.4859) -> (93.6486, 22.7176, -1.4859)
  line L387 (93.6486, 22.7176, -1.4859) -> (93.8351, 22.657, -1.4859)
  line L388 (93.8351, 22.657, -1.4859) -> (94.0099, 22.5679, -1.4859)
  line L389 (94.0099, 22.5679, -1.4859) -> (94.1686, 22.4526, -1.4859)
  line L390 (94.1686, 22.4526, -1.4859) -> (94.3073, 22.3139, -1.4859)
  line L391 (94.3073, 22.3139, -1.4859) -> (94.4226, 22.1552, -1.4859)
  line L392 (94.4226, 22.1552, -1.4859) -> (94.5116, 21.9805, -1.4859)
  line L393 (94.5116, 21.9805, -1.4859) -> (94.5722, 21.7939, -1.4859)
  line L394 (94.5722, 21.7939, -1.4859) -> (94.6029, 21.6002, -1.4859)
  line L395 (94.6029, 21.6002, -1.4859) -> (94.6068, 21.5021, -1.4859)
  line L396 (94.6068, 21.5021, -1.4859) -> (94.6068, 21.0021, -1.4859)
  line L397 (94.6068, 21.0021, -1.4859) -> (94.6029, 20.904, -1.4859)
  line L398 (94.6029, 20.904, -1.4859) -> (94.5722, 20.7103, -1.4859)
  line L399 (94.5722, 20.7103, -1.4859) -> (94.5116, 20.5238, -1.4859)
  line L400 (94.5116, 20.5238, -1.4859) -> (94.4226, 20.349, -1.4859)
  line L401 (94.4226, 20.349, -1.4859) -> (94.3073, 20.1903, -1.4859)
  line L402 (94.3073, 20.1903, -1.4859) -> (94.1686, 20.0516, -1.4859)
  line L403 (94.1686, 20.0516, -1.4859) -> (94.0099, 19.9363, -1.4859)
  line L404 (94.0099, 19.9363, -1.4859) -> (93.9568, 19.9092, -1.4859)
  line L405 (93.9568, 19.9092, -1.4859) -> (93.9568, 17.1305, -1.4859)
  line L406 (93.9568, 17.1305, -1.4859) -> (97.5059, 13.5813, -1.4859)
  line L407 (97.5059, 13.5813, -1.4859) -> (97.5487, 13.5881, -1.4859)
  line L408 (97.5487, 13.5881, -1.4859) -> (97.6467, 13.592, -1.4859)
  line L409 (97.6467, 13.592, -1.4859) -> (98.1467, 13.592, -1.4859)
  line L410 (98.1467, 13.592, -1.4859) -> (98.2448, 13.5881, -1.4859)
  line L411 (98.2448, 13.5881, -1.4859) -> (98.4385, 13.5574, -1.4859)
  line L412 (98.4385, 13.5574, -1.4859) -> (98.6251, 13.4968, -1.4859)
  line L413 (98.6251, 13.4968, -1.4859) -> (98.7999, 13.4078, -1.4859)
  line L414 (98.7999, 13.4078, -1.4859) -> (98.9586, 13.2925, -1.4859)
  line L415 (98.9586, 13.2925, -1.4859) -> (99.0972, 13.1538, -1.4859)
  line L416 (99.0972, 13.1538, -1.4859) -> (99.2125, 12.9951, -1.4859)
  line L417 (99.2125, 12.9951, -1.4859) -> (99.3016, 12.8203, -1.4859)
  line L418 (99.3016, 12.8203, -1.4859) -> (99.3622, 12.6338, -1.4859)
  line L419 (99.3622, 12.6338, -1.4859) -> (99.3929, 12.44, -1.4859)
  line L420 (99.3929, 12.44, -1.4859) -> (99.3929, 12.2439, -1.4859)
  line L421 (99.3929, 12.2439, -1.4859) -> (99.3622, 12.0501, -1.4859)
  line L422 (99.3622, 12.0501, -1.4859) -> (99.3016, 11.8636, -1.4859)
  line L423 (99.3016, 11.8636, -1.4859) -> (99.2125, 11.6888, -1.4859)
  line L424 (99.2125, 11.6888, -1.4859) -> (99.0972, 11.5301, -1.4859)
  line L425 (99.0972, 11.5301, -1.4859) -> (98.9586, 11.3914, -1.4859)
  line L426 (98.9586, 11.3914, -1.4859) -> (98.7999, 11.2762, -1.4859)
  line L427 (98.7999, 11.2762, -1.4859) -> (98.6251, 11.1871, -1.4859)
  line L428 (98.6251, 11.1871, -1.4859) -> (98.4385, 11.1265, -1.4859)
  line L429 (98.4385, 11.1265, -1.4859) -> (98.2448, 11.0958, -1.4859)
  line L430 (98.2448, 11.0958, -1.4859) -> (98.1467, 11.092, -1.4859)
  line L431 (98.1467, 11.092, -1.4859) -> (97.6467, 11.092, -1.4859)
  line L432 (97.6467, 11.092, -1.4859) -> (97.5487, 11.0958, -1.4859)
  line L433 (97.5487, 11.0958, -1.4859) -> (97.3549, 11.1265, -1.4859)
  line L434 (97.3549, 11.1265, -1.4859) -> (97.1684, 11.1871, -1.4859)
  line L435 (97.1684, 11.1871, -1.4859) -> (96.9936, 11.2762, -1.4859)
  line L436 (96.9936, 11.2762, -1.4859) -> (96.8349, 11.3915, -1.4859)
  line L437 (96.8349, 11.3915, -1.4859) -> (96.6962, 11.5301, -1.4859)
  line L438 (96.6962, 11.5301, -1.4859) -> (96.5809, 11.6888, -1.4859)
  line L439 (96.5809, 11.6888, -1.4859) -> (96.4919, 11.8636, -1.4859)
  line L440 (96.4919, 11.8636, -1.4859) -> (96.4313, 12.0501, -1.4859)
  line L441 (96.4313, 12.0501, -1.4859) -> (96.4006, 12.2439, -1.4859)
  line L442 (96.4006, 12.2439, -1.4859) -> (96.4006, 12.44, -1.4859)
  line L443 (96.4006, 12.44, -1.4859) -> (96.4313, 12.6338, -1.4859)
  line L444 (96.4313, 12.6338, -1.4859) -> (96.4919, 12.8203, -1.4859)
  line L445 (96.4919, 12.8203, -1.4859) -> (96.5182, 12.872, -1.4859)
  line L446 (96.5182, 12.872, -1.4859) -> (92.9325, 16.4577, -1.4859)
  line L447 (92.9325, 16.4577, -1.4859) -> (92.8808, 16.5167, -1.4859)
  line L448 (92.8808, 16.5167, -1.4859) -> (92.8024, 16.6523, -1.4859)
  line L449 (92.8024, 16.6523, -1.4859) -> (92.7619, 16.8036, -1.4859)
  line L450 (92.7619, 16.8036, -1.4859) -> (92.7568, 16.8819, -1.4859)
  line L451 (92.7568, 16.8819, -1.4859) -> (92.7568, 19.9092, -1.4859)
  line L452 (92.7568, 19.9092, -1.4859) -> (92.7036, 19.9363, -1.4859)
  line L453 (92.7036, 19.9363, -1.4859) -> (92.545, 20.0516, -1.4859)
  line L454 (92.545, 20.0516, -1.4859) -> (92.4063, 20.1903, -1.4859)
  line L455 (92.4063, 20.1903, -1.4859) -> (92.291, 20.349, -1.4859)
  line L456 (92.291, 20.349, -1.4859) -> (92.2019, 20.5238, -1.4859)
  line L457 (92.2019, 20.5238, -1.4859) -> (92.1602, 20.6521, -1.4859)
  line L458 (92.1602, 20.6521, -1.4859) -> (88.8233, 20.6521, -1.4859)
  line L459 (88.8233, 20.6521, -1.4859) -> (88.745, 20.6572, -1.4859)
  line L460 (88.745, 20.6572, -1.4859) -> (88.5937, 20.6978, -1.4859)
  line L461 (88.5937, 20.6978, -1.4859) -> (88.4581, 20.7761, -1.4859)
  line L462 (88.4581, 20.7761, -1.4859) -> (88.3991, 20.8278, -1.4859)
  line L463 (88.3991, 20.8278, -1.4859) -> (84.8488, 24.3781, -1.4859)
  line L464 (84.8488, 24.3781, -1.4859) -> (75.5, 24.3781, -1.4859)
  line L465 (75.5, 24.3781, -1.4859) -> (75.4216, 24.3832, -1.4859)
  line L466 (75.4216, 24.3832, -1.4859) -> (75.2704, 24.4237, -1.4859)
  line L467 (75.2704, 24.4237, -1.4859) -> (75.1347, 24.5021, -1.4859)
  line L468 (75.1347, 24.5021, -1.4859) -> (75.0757, 24.5538, -1.4859)
  line L469 (75.0757, 24.5538, -1.4859) -> (71.8603, 27.7692, -1.4859)
  line L470 (71.8603, 27.7692, -1.4859) -> (69.9838, 27.7692, -1.4859)
  line L471 (69.9838, 27.7692, -1.4859) -> (69.9838, 30.2192, -1.4859)
  line L472 (69.9838, 30.2192, -1.4859) -> (72.9838, 30.2192, -1.4859)
  line L473 (72.9838, 30.2192, -1.4859) -> (72.9838, 28.3427, -1.4859)
  line L474 (43.7633, 16.6136, -1.4859) -> (43.9556, 16.5753, -1.4859)
  line L475 (43.9556, 16.5753, -1.4859) -> (44.1367, 16.5003, -1.4859)
  line L476 (44.1367, 16.5003, -1.4859) -> (44.2997, 16.3914, -1.4859)
  line L477 (44.2997, 16.3914, -1.4859) -> (44.4383, 16.2528, -1.4859)
  line L478 (44.4383, 16.2528, -1.4859) -> (44.5472, 16.0898, -1.4859)
  line L479 (44.5472, 16.0898, -1.4859) -> (44.6222, 15.9087, -1.4859)
  line L480 (44.6222, 15.9087, -1.4859) -> (44.6605, 15.7164, -1.4859)
  line L481 (44.6605, 15.7164, -1.4859) -> (44.6605, 15.5204, -1.4859)
  line L482 (44.6605, 15.5204, -1.4859) -> (44.6222, 15.3281, -1.4859)
  line L483 (44.6222, 15.3281, -1.4859) -> (44.5472, 15.147, -1.4859)
  line L484 (44.5472, 15.147, -1.4859) -> (44.4383, 14.984, -1.4859)
  line L485 (44.4383, 14.984, -1.4859) -> (44.2997, 14.8454, -1.4859)
  line L486 (44.2997, 14.8454, -1.4859) -> (44.1367, 14.7365, -1.4859)
  line L487 (44.1367, 14.7365, -1.4859) -> (43.9556, 14.6615, -1.4859)
  line L488 (43.9556, 14.6615, -1.4859) -> (43.7633, 14.6232, -1.4859)
  line L489 (43.7633, 14.6232, -1.4859) -> (43.6653, 14.6184, -1.4859)
  line L490 (43.6653, 14.6184, -1.4859) -> (42.4653, 14.6184, -1.4859)
  line L491 (42.4653, 14.6184, -1.4859) -> (42.3673, 14.6232, -1.4859)
  line L492 (42.3673, 14.6232, -1.4859) -> (42.175, 14.6615, -1.4859)
  line L493 (42.175, 14.6615, -1.4859) -> (41.9939, 14.7365, -1.4859)
  line L494 (41.9939, 14.7365, -1.4859) -> (41.8309, 14.8454, -1.4859)
  line L495 (41.8309, 14.8454, -1.4859) -> (41.6923, 14.984, -1.4859)
  line L496 (41.6923, 14.984, -1.4859) -> (41.5834, 15.147, -1.4859)
  line L497 (41.5834, 15.147, -1.4859) -> (41.5083, 15.3281, -1.4859)
  line L498 (41.5083, 15.3281, -1.4859) -> (41.4701, 15.5204, -1.4859)
  line L499 (41.4701, 15.5204, -1.4859) -> (41.4701, 15.7164, -1.4859)
  line L500 (41.4701, 15.7164, -1.4859) -> (41.5083, 15.9087, -1.4859)
  line L501 (41.5083, 15.9087, -1.4859) -> (41.5834, 16.0898, -1.4859)
  line L502 (41.5834, 16.0898, -1.4859) -> (41.6923, 16.2528, -1.4859)
  line L503 (41.6923, 16.2528, -1.4859) -> (41.8309, 16.3914, -1.4859)
  line L504 (41.8309, 16.3914, -1.4859) -> (41.9939, 16.5003, -1.4859)
  line L505 (41.9939, 16.5003, -1.4859) -> (42.175, 16.5753, -1.4859)
  line L506 (42.175, 16.5753, -1.4859) -> (42.3673, 16.6136, -1.4859)
  line L507 (42.3673, 16.6136, -1.4859) -> (42.4653, 16.6184, -1.4859)
  line L508 (42.4653, 16.6184, -1.4859) -> (43.6653, 16.6184, -1.4859)
  line L509 (43.6653, 16.6184, -1.4859) -> (43.7633, 16.6136, -1.4859)
  line L510 (104.7233, 16.6136, -1.4859) -> (104.9156, 16.5753, -1.4859)
  line L511 (104.9156, 16.5753, -1.4859) -> (105.0967, 16.5003, -1.4859)
  line L512 (105.0967, 16.5003, -1.4859) -> (105.2597, 16.3914, -1.4859)
  line L513 (105.2597, 16.3914, -1.4859) -> (105.3983, 16.2528, -1.4859)
  line L514 (105.3983, 16.2528, -1.4859) -> (105.5072, 16.0898, -1.4859)
  line L515 (105.5072, 16.0898, -1.4859) -> (105.5822, 15.9087, -1.4859)
  line L516 (105.5822, 15.9087, -1.4859) -> (105.6205, 15.7164, -1.4859)
  line L517 (105.6205, 15.7164, -1.4859) -> (105.6205, 15.5204, -1.4859)
  line L518 (105.6205, 15.5204, -1.4859) -> (105.5822, 15.3281, -1.4859)
  line L519 (105.5822, 15.3281, -1.4859) -> (105.5072, 15.147, -1.4859)
  line L520 (105.5072, 15.147, -1.4859) -> (105.3983, 14.984, -1.4859)
  line L521 (105.3983, 14.984, -1.4859) -> (105.2597, 14.8454, -1.4859)
  line L522 (105.2597, 14.8454, -1.4859) -> (105.0967, 14.7365, -1.4859)
  line L523 (105.0967, 14.7365, -1.4859) -> (104.9156, 14.6615, -1.4859)
  line L524 (104.9156, 14.6615, -1.4859) -> (104.7233, 14.6232, -1.4859)
  line L525 (104.7233, 14.6232, -1.4859) -> (104.6253, 14.6184, -1.4859)
  line L526 (104.6253, 14.6184, -1.4859) -> (103.4253, 14.6184, -1.4859)
  line L527 (103.4253, 14.6184, -1.4859) -> (103.3273, 14.6232, -1.4859)
  line L528 (103.3273, 14.6232, -1.4859) -> (103.135, 14.6615, -1.4859)
  line L529 (103.135, 14.6615, -1.4859) -> (102.9539, 14.7365, -1.4859)
  line L530 (102.9539, 14.7365, -1.4859) -> (102.7909, 14.8454, -1.4859)
  line L531 (102.7909, 14.8454, -1.4859) -> (102.6523, 14.984, -1.4859)
  line L532 (102.6523, 14.984, -1.4859) -> (102.5434, 15.147, -1.4859)
  line L533 (102.5434, 15.147, -1.4859) -> (102.4683, 15.3281, -1.4859)
  line L534 (102.4683, 15.3281, -1.4859) -> (102.4301, 15.5204, -1.4859)
  line L535 (102.4301, 15.5204, -1.4859) -> (102.4301, 15.7164, -1.4859)
  line L536 (102.4301, 15.7164, -1.4859) -> (102.4683, 15.9087, -1.4859)
  line L537 (102.4683, 15.9087, -1.4859) -> (102.5434, 16.0898, -1.4859)
  line L538 (102.5434, 16.0898, -1.4859) -> (102.6523, 16.2528, -1.4859)
  line L539 (102.6523, 16.2528, -1.4859) -> (102.7909, 16.3914, -1.4859)
  line L540 (102.7909, 16.3914, -1.4859) -> (102.9539, 16.5003, -1.4859)
  line L541 (102.9539, 16.5003, -1.4859) -> (103.135, 16.5753, -1.4859)
  line L542 (103.135, 16.5753, -1.4859) -> (103.3273, 16.6136, -1.4859)
  line L543 (103.3273, 16.6136, -1.4859) -> (103.4253, 16.6184, -1.4859)
  line L544 (103.4253, 16.6184, -1.4859) -> (104.6253, 16.6184, -1.4859)
  line L545 (104.6253, 16.6184, -1.4859) -> (104.7233, 16.6136, -1.4859)
  line L546 (21.9361, 18.9762, -1.4859) -> (22.126, 18.9462, -1.4859)
  line L547 (22.126, 18.9462, -1.4859) -> (22.3088, 18.8868, -1.4859)
  line L548 (22.3088, 18.8868, -1.4859) -> (22.4801, 18.7995, -1.4859)
  line L549 (22.4801, 18.7995, -1.4859) -> (22.6356, 18.6865, -1.4859)
  line L550 (22.6356, 18.6865, -1.4859) -> (22.7715, 18.5506, -1.4859)
  line L551 (22.7715, 18.5506, -1.4859) -> (22.8845, 18.3951, -1.4859)
  line L552 (22.8845, 18.3951, -1.4859) -> (22.9718, 18.2238, -1.4859)
  line L553 (22.9718, 18.2238, -1.4859) -> (23.0312, 18.041, -1.4859)
  line L554 (23.0312, 18.041, -1.4859) -> (23.0612, 17.8511, -1.4859)
  line L555 (23.0612, 17.8511, -1.4859) -> (23.0612, 17.6589, -1.4859)
  line L556 (23.0612, 17.6589, -1.4859) -> (23.0312, 17.469, -1.4859)
  line L557 (23.0312, 17.469, -1.4859) -> (22.9718, 17.2862, -1.4859)
  line L558 (22.9718, 17.2862, -1.4859) -> (22.8845, 17.1149, -1.4859)
  line L559 (22.8845, 17.1149, -1.4859) -> (22.7715, 16.9594, -1.4859)
  line L560 (22.7715, 16.9594, -1.4859) -> (22.6356, 16.8235, -1.4859)
  line L561 (22.6356, 16.8235, -1.4859) -> (22.4801, 16.7105, -1.4859)
  line L562 (22.4801, 16.7105, -1.4859) -> (22.3088, 16.6232, -1.4859)
  line L563 (22.3088, 16.6232, -1.4859) -> (22.126, 16.5638, -1.4859)
  line L564 (22.126, 16.5638, -1.4859) -> (21.9361, 16.5338, -1.4859)
  line L565 (21.9361, 16.5338, -1.4859) -> (21.84, 16.53, -1.4859)
  line L566 (21.84, 16.53, -1.4859) -> (21.29, 16.53, -1.4859)
  line L567 (21.29, 16.53, -1.4859) -> (21.1939, 16.5338, -1.4859)
  line L568 (21.1939, 16.5338, -1.4859) -> (21.004, 16.5638, -1.4859)
  line L569 (21.004, 16.5638, -1.4859) -> (20.8212, 16.6232, -1.4859)
  line L570 (20.8212, 16.6232, -1.4859) -> (20.6499, 16.7105, -1.4859)
  line L571 (20.6499, 16.7105, -1.4859) -> (20.4944, 16.8235, -1.4859)
  line L572 (20.4944, 16.8235, -1.4859) -> (20.3585, 16.9594, -1.4859)
  line L573 (20.3585, 16.9594, -1.4859) -> (20.2455, 17.1149, -1.4859)
  line L574 (20.2455, 17.1149, -1.4859) -> (20.1582, 17.2862, -1.4859)
  line L575 (20.1582, 17.2862, -1.4859) -> (20.0988, 17.469, -1.4859)
  line L576 (20.0988, 17.469, -1.4859) -> (20.0688, 17.6589, -1.4859)
  line L577 (20.0688, 17.6589, -1.4859) -> (20.0688, 17.8511, -1.4859)